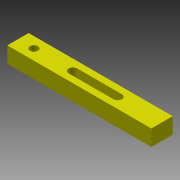
# Autodesk Inventor part: bocnice
Saved by Autodesk Inventor 2014 (Build 180170000, 170)
## iProperties
Created: 2014-09-19
Part Number: bocnice
Material: Všeobecné
Document SubType Name: Modeling
Designer: brodhaq
Density: 1 g/cm^3
Appearance: Výchozí
Author: brodhaq
Autodesk Inventor part; units mm, degrees
ref_plane "YZ Plane" through (0, 0, 0) normal (1, 0, 0) x (0, 1, 0)
ref_plane "XZ Plane" through (0, 0, 0) normal (0, 1, 0) x (-1, 0, 0)
ref_plane "XY Plane" through (0, 0, 0) normal (0, 0, 1) x (1, 0, 0)
sketch "Náčrt1" plane through (0, 0, 0) normal (0, 0, 1) x (1, 0, 0)
  line L0 (-8.5677, 4) -> (45.4323, 4)
  line L1 (45.4323, 4) -> (45.4323, -4)
  line L2 (45.4323, -4) -> (-8.5677, -4)
  line L3 (-8.5677, -4) -> (-8.5677, 4)
  line L4 (12.0323, 1.6) -> (28.8323, 1.6)
  line L5 (28.8323, -1.6) -> (12.0323, -1.6)
  arc A0 (12.0323, 1.6) -> (12.0323, -1.6) centre (12.0323, 0) ccw
  arc A1 (28.8323, -1.6) -> (28.8323, 1.6) centre (28.8323, 0) ccw
  circle A2 centre (-2.5677, 0) radius 1.5
  point P0 (0, 0)
  point P1 (-8.5677, 0)
  dimension "d0" = 8
  dimension "d1" = 54
  dimension "d2" = 3.2
  dimension "d3" = 0
  dimension "d4" = 0
  dimension "d5" = 15
  dimension "d6" = 20
  dimension "d9" = 3
  dimension "d10" = 6
  constraints: 12 end point, 4 point on circle, 4 tangent, 3 centre point, 3 parallel, 2 horizontal, 1 midpoint, 1 perpendicular
  measures "d0" distance of L0.end L1.end
  measures "d1" distance of L1.end L2.end
  measures "d2" distance between parallel lines of L5 L4
  measures "d3" vertical distance of point (0, 0) A0.centre
  measures "d4" vertical distance of A0.centre point (-8.568, 0)
  measures "d5" distance edge to line of A1 L1
  measures "d9" diameter of A2
  measures "d10" distance from line of L3 A2.centre
extrude "Vysunutí2" add sketch "Náčrt1" along normal blind 6
